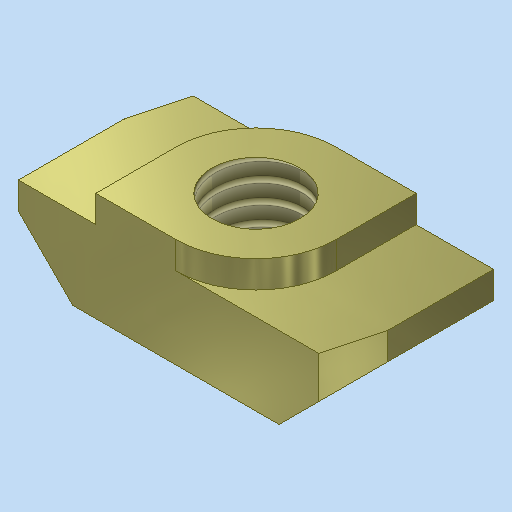
# Autodesk Inventor part: 3842523135_050824_001
Saved by Autodesk Inventor 2023.3 (Build 273359000, 359)
## iProperties
Shininess: 20.0
Length Units: 11269
Angle Units: 11279
Time Units: 11290
Mass Units: 11283
Length Display Precision: 3
Angle Display Precision: 2
Created: 2002-10-08
Part Number: 3842523135_050824_001
Material: Allgemein
Document SubType Name: Modellieren
Description: =<RBPARTNOTITLE2>
Vendor: Bosch Rexroth
Density: 1 g/cm^3
Mass: 0.178512 g
Surface Area: 2.62658 cm^2
Volume: 0.178512 cm^3
Appearance: Nickel (glänzend)
GAIN_REFID: 20__3842523135_050824_001:42E1A
Control State: 0
Master: False
Checked Out: False
RBPARTNOTITLE2: Hammermutter M4
RBPARTMADEOF: 3 842 523 135
RBDRAWINGMISSINGSPEC: --
AnP_Kategorie: 2
Density: 0.0
Volumn: 0.0
Area: 0.0
PropertySet Name: Model Information
Keywords: =<RBPARTMADEOF>
Comments: =<RBSURFACE2>
Revision Number: 01
Autodesk Inventor part; units mm, degrees
ref_plane "YZ Ebene" through (0, 0, 0) normal (1, 0, 0) x (0, 1, 0)
ref_plane "XZ Ebene" through (0, 0, 0) normal (0, 1, 0) x (-1, 0, 0)
ref_plane "XY Ebene" through (0, 0, 0) normal (0, 0, 1) x (1, 0, 0)
sketch "Skizze1" plane through (0, 0, 0) normal (0, 0, 1) x (1, 0, 0)
  line L0 (0, -0.0604) -> (11.6, -0.0604)
  line L1 (11.6, -0.0604) -> (11.6, 5.8396)
  line L2 (11.6, 5.8396) -> (0, 5.8396)
  line L3 (0, 5.8396) -> (0, -0.0604)
  dimension "d0" = 11.6
  dimension "d1" = 5.9
  constraints: 8 end point, 2 parallel, 1 horizontal, 1 perpendicular, 1 other
  measures "d0" distance of L1.end L2.end
  measures "d1" distance of L0.end L1.end
extrude "Extrusion1" add sketch "Skizze1" along normal blind 3
sketch "Skizze2" plane through (0, 0, 3) normal (0, 0, 1) x (1, 0, 0)
  line L0 (0, -0.0604) -> (0, 5.8396) projected
  line L1 (11.6, -0.0604) -> (0, -0.0604) projected
  line L2 (11.6, 5.8396) -> (11.6, -0.0604) projected
  line L3 (0, 5.8396) -> (11.6, 5.8396) projected
  line L4 (2.85, -0.0604) -> (8.75, -0.0604)
  line L5 (8.75, -0.0604) -> (8.75, 5.8396)
  line L6 (8.75, 5.8396) -> (2.85, 5.8396)
  line L7 (2.85, 5.8396) -> (2.85, -0.0604)
  dimension "d4" = 5.9
  dimension "d5" = 2.85
  constraints: 8 end point, 2 parallel, 2 point on line, 1 horizontal, 1 perpendicular
  measures "d4" distance of L5.end L6.end
  measures "d5" distance between parallel lines of L2 L5
extrude "Extrusion2" add sketch "Skizze2" along normal blind 1 contours L7 L3 L5 L1
chamfer "Fase1" distance 2 angle 45 2 edges at (0, 2.8896, 0) (11.6, 2.8896, 0)
fillet "Rundung1" radius 2.95 2 edges at (2.85, 5.8396, 3.5) (8.75, -0.0604, 3.5)
chamfer "Fase2" distance 2 angle 15 1 edges at (11.6, -0.0604, 2.5) measured on face at (11.6, 1.9063, 2.3333)
chamfer "Fase3" distance 2 angle 15 1 edges at (0, 5.8396, 2.5) measured on face at (0, 3.873, 2.3333)
sketch "Skizze3" plane through (0, 0, 4) normal (0, 0, 1) x (1, 0, 0)
  arc A0 (5.8, 5.8396) -> (2.85, 2.8896) centre (5.8, 2.8896) ccw projected
  constraints: 1 coincident
hole "Bohrung1" at (5.8, 2.8896, 4) direction (0, 0, -1) diameter 3.242 end through all thread size "M4x0.7" class "6H" standard "ANSI Metrisches M Profil"
equation "\"d4\" = d1"
equation "\"d5\" = -0.5 * d1 + 0.5 * d0"
equation "\"d10\" = 0.5 * d1"
